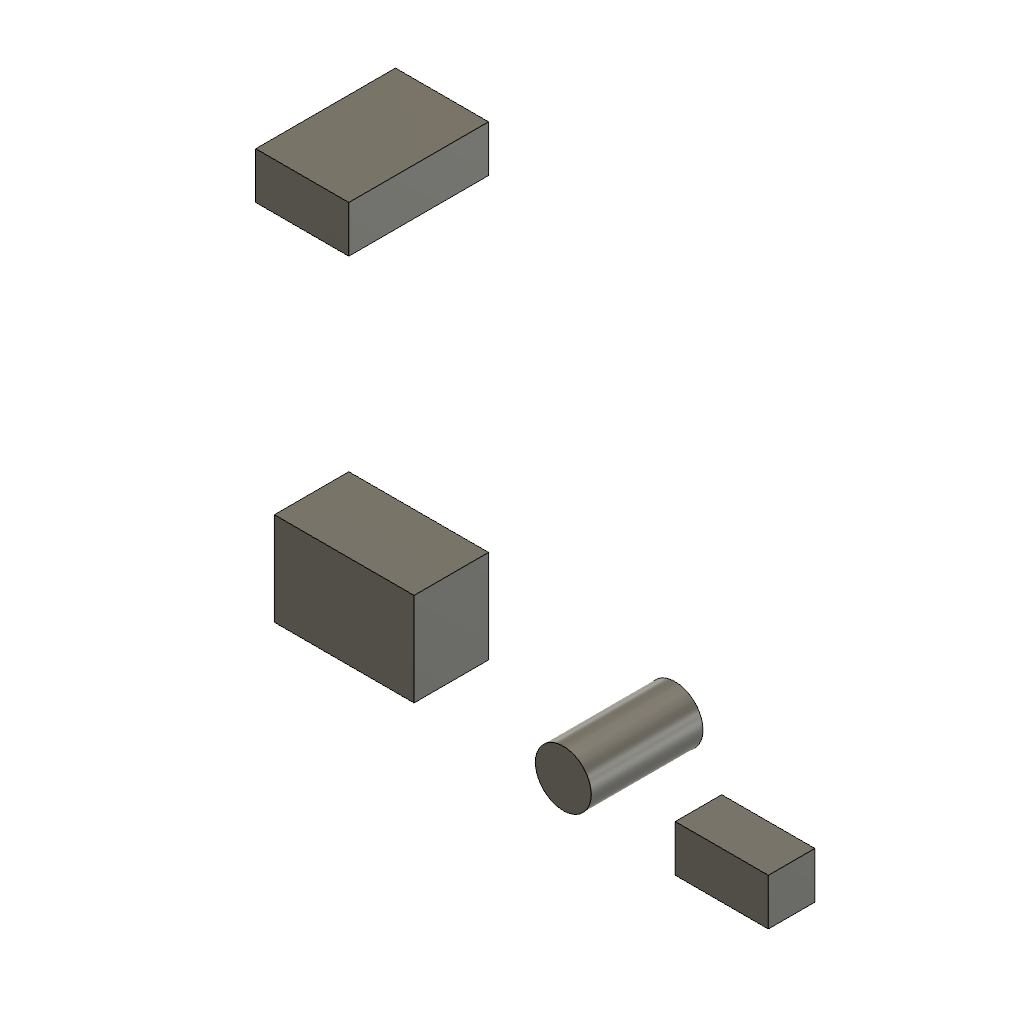
vendor_SnapshotFallbackControlSaved (Autodesk Fusion 360 design; units mm, degrees)
part number: 2026-10-20-19-50-30-542
part number: 2026-10-20-19-50-31-658
part number: 2026-10-20-19-50-31-685
Autodesk Fusion 360 part; units mm, degrees
sketch "Sketch1" plane through (0, 0, 0) normal (0, 0, 1) x (1, 0, 0)
  line L0 (10, 10) -> (40, 10)
  line L1 (40, 10) -> (40, 30)
  line L2 (40, 30) -> (10, 30)
  line L3 (10, 30) -> (10, 10)
extrude "Extrude1" add sketch "Sketch1" along normal blind 16 makes body 1
sketch "Sketch1 (2)" plane through (0, 0, 0) normal (0, 0, 1) x (1, 0, 0) in component "Module A"
  line L0 (-10, 0) -> (10, 0)
  line L1 (10, 0) -> (10, 10)
  line L2 (10, 10) -> (-10, 10)
  line L3 (-10, 10) -> (-10, 0)
extrude "Extrude1'" add sketch "Sketch1 (2)" along normal blind 10 separate body makes body 2 in component "Module A"
sketch "Sketch2" plane through (0, 0, 0) normal (0, 0, 1) x (1, 0, 0)
  circle A0 centre (80, 20) radius 6
extrude "Extrude2" add sketch "Sketch2" along normal blind 24 separate body makes body 3
sketch "Sketch1 (3)" plane through (0, 0, 0) normal (0, 0, 1) x (1, 0, 0) in component "Module B"
  line L0 (20, -20) -> (40, -20)
  line L1 (40, -20) -> (40, -10)
  line L2 (40, -10) -> (20, -10)
  line L3 (20, -10) -> (20, -20)
extrude "Extrude1''" add sketch "Sketch1 (3)" along normal blind 30 separate body makes body 4 in component "Module B"
component "Module A" placed x (1, 0, 0) y (0, 1, 0) z (0, 0, 1) at (100, 0, 0)
component "Module B" placed x (1, 0, 0) y (0, 1, 0) z (0, 0, 1) at (0, 120, 0)
named bodies: "Root block", "Child bracket", "Guide pin Ø12", "Child spacer"
